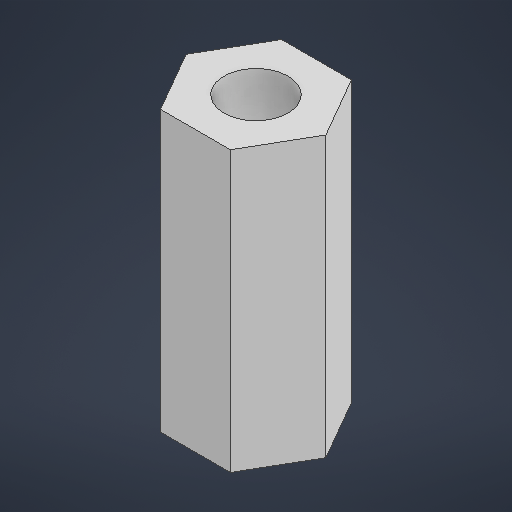
# Autodesk Inventor part: Screw Peg
Saved by Autodesk Inventor 2026.2 (Build 302298010, 298A)
## iProperties
Created: 2026-05-14
Part Number: Screw Peg
Material: Generic
Document SubType Name: Modeling
Designer: User
Density: 1 g/cm^3
Appearance: Default
Author: User
Autodesk Inventor part; units mm, degrees
ref_plane "YZ Plane" through (0, 0, 0) normal (1, 0, 0) x (0, 1, 0)
ref_plane "XZ Plane" through (0, 0, 0) normal (0, 1, 0) x (-1, 0, 0)
ref_plane "XY Plane" through (0, 0, 0) normal (0, 0, 1) x (1, 0, 0)
sketch "Sketch1" plane through (0, 0, 0) normal (0, 1, 0) x (-1, 0, 0)
  line L0 (-3, 0) -> (-1.5, -2.5981)
  line L1 (-1.5, -2.5981) -> (1.5, -2.5981)
  line L2 (1.5, -2.5981) -> (3, 0)
  line L3 (3, 0) -> (1.5, 2.5981)
  line L4 (3, 0) -> (6, 0) construction
  line L5 (1.5, 2.5981) -> (-1.5, 2.5981)
  line L6 (-1.5, 2.5981) -> (-3, 0)
  point P0 (0, 0)
  point P1 (0, 0)
  dimension "d1" = 3
  dimension "d3" = 3
  dimension "d4" = 3
  dimension "d5" = 120
  dimension "d6" = 3
  dimension "d7" = 120
  constraints: 14 end point, 1 coincident, 1 equal length, 1 horizontal, 1 parallel
  measures "d1" distance of L0.start L0.end
  measures "d3" distance of L0.end L1.end
  measures "d4" distance of L1.end L2.end
  measures "d5" angle of L2 L1
  measures "d6" distance of L2.end L3.end
  measures "d7" angle of L4 L3
extrude "Extrusion1" add sketch "Sketch1" along normal blind 12
sketch "Sketch2" plane through (0, 12, 0) normal (0, 1, 0) x (1, 0, 0)
  point P0 (0, 0)
  point P1 (0, 0)
  constraints: 1 coincident
hole "Hole1" at (0, 12, 0) direction (0, -1, 0) diameter 2.75 end through all
body "Solid1"
